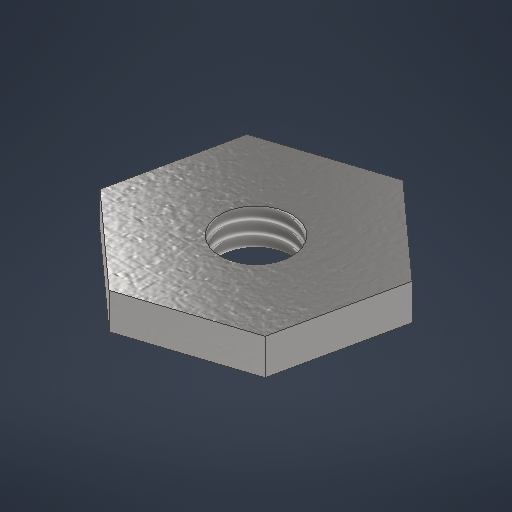
# Autodesk Inventor part: Part4
Saved by Autodesk Inventor 2026 (Build 300175000, 175)
## iProperties
Created: 2025-12-18
Part Number: Part4
Material: Generic
Document SubType Name: Modeling
Designer: MSI NOTEBOOK
Density: 1 g/cm^3
Appearance: Default
Author: MSI NOTEBOOK
Autodesk Inventor part; units mm, degrees
ref_plane "YZ Plane" through (0, 0, 0) normal (1, 0, 0) x (0, 1, 0)
ref_plane "XZ Plane" through (0, 0, 0) normal (0, 1, 0) x (-1, 0, 0)
ref_plane "XY Plane" through (0, 0, 0) normal (0, 0, 1) x (1, 0, 0)
sketch "Sketch1" plane through (0, 0, 0) normal (0, 1, 0) x (-1, 0, 0)
  line L0 (-1.4375, -6.7478) -> (-6.5625, -2.129)
  line L1 (-6.5625, -2.129) -> (-5.1251, 4.6188)
  line L2 (-5.1251, 4.6188) -> (1.4375, 6.7478)
  line L3 (1.4375, 6.7478) -> (6.5625, 2.129)
  line L4 (6.5625, 2.129) -> (5.1251, -4.6188)
  line L5 (5.1251, -4.6188) -> (-1.4375, -6.7478)
  point P0 (0, 0)
  point P1 (0, 0)
  point P2 (4, 4.4384)
  dimension "d1" = 4
  constraints: 12 end point, 1 coincident, 1 midpoint, 13 other
  measures "d1" horizontal distance of point (4, 4.438) point (0, 0)
extrude "Extrusion1" add sketch "Sketch1" along normal blind 2
sketch "Sketch2" plane through (0, 2, 0) normal (0, 1, 0) x (1, 0, 0)
  circle A0 centre (0, 0) radius 2
  dimension "d4" = 4
  constraints: 1 centre point, 1 coincident
  measures "d4" diameter of A0
extrude "Extrusion2" cut sketch "Sketch2" against normal through all
thread "Thread1" size "M4x0.7" class "6H" standard "ANSI Metric M Profile" full length
body "Solid1"
